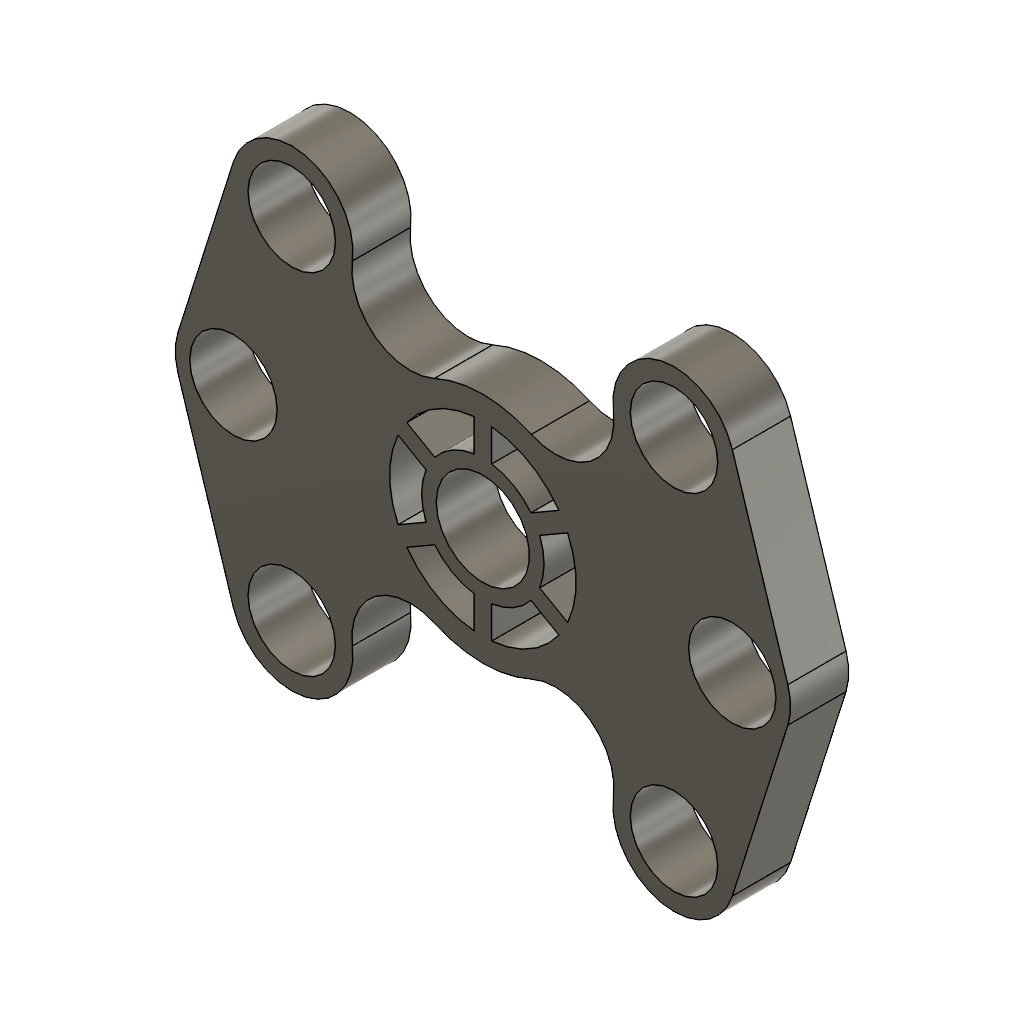
ex1.2 (Autodesk Fusion 360 design; units mm, degrees)
part number: 2026-10-12-15-41-16-369
Autodesk Fusion 360 part; units mm, degrees
sketch "Sketch1" plane through (0, 0, 0) normal (0, 0, 1) x (1, 0, 0)
  circle A0 centre (0, 0) radius 16
  circle A1 centre (0, 0) radius 40
  line L0 (-3, 20.7846) -> (-3, 31.8591)
  line L1 (-16.5, -12.9904) -> (-26.0908, -18.5276)
  line L2 (19.5, -7.7942) -> (29.0908, -13.3315)
  line L3 (3, 20.7846) -> (3, 31.8591)
  line L4 (-19.5, 7.7942) -> (-29.0908, 13.3315)
  line L5 (-16.5, 12.9904) -> (-26.0908, 18.5276)
  line L6 (-19.5, -7.7942) -> (-29.0908, -13.3315)
  line L7 (3, -20.7846) -> (3, -31.8591)
  line L8 (-3, -20.7846) -> (-3, -31.8591)
  line L9 (19.5, -7.7942) -> (29.0908, -13.3315)
  line L10 (16.5, -12.9904) -> (26.0908, -18.5276)
  line L11 (16.5, 12.9904) -> (26.0908, 18.5276)
  line L12 (19.5, 7.7942) -> (29.0908, 13.3315)
  line L13 (0, 60) -> (0, 40)
  line L14 (0, 60) -> (0, 40)
  arc A2 (16.5, 12.9904) -> (3, 20.7846) centre (0, 0) ccw
  arc A3 (26.0908, 18.5276) -> (3, 31.8591) centre (0, 0) ccw
  arc A4 (-3, 31.8591) -> (-26.0908, 18.5276) centre (0, 0) ccw
  arc A5 (-3, 20.7846) -> (-16.5, 12.9904) centre (0, 0) ccw
  arc A6 (-19.5, 7.7942) -> (-19.5, -7.7942) centre (0, 0) ccw
  arc A7 (-29.0908, 13.3315) -> (-29.0908, -13.3315) centre (0, 0) ccw
  arc A8 (19.5, -7.7942) -> (19.5, 7.7942) centre (0, 0) ccw
  arc A9 (29.0908, -13.3315) -> (29.0908, 13.3315) centre (0, 0) ccw
  arc A10 (-16.5, -12.9904) -> (-3, -20.7846) centre (0, 0) ccw
  arc A11 (3, -20.7846) -> (16.5, -12.9904) centre (0, 0) ccw
  arc A12 (-26.0908, -18.5276) -> (-3, -31.8591) centre (0, 0) ccw
  arc A13 (3, -31.8591) -> (26.0908, -18.5276) centre (0, 0) ccw
  line L15 (0, 16) -> (0, -16)
  line L16 (0, -40) -> (0, -55)
  line L17 (0, 16) -> (0, -16)
  line L18 (0, -40) -> (0, -55)
  line L19 (0, 0) -> (-65.5914, 0)
  line L20 (-65.5914, 0) -> (-85.5914, 0)
  circle A14 centre (-65.5914, 60) radius 15
  circle A15 centre (-65.5914, 60) radius 21
  circle A16 centre (-85.5914, 0) radius 15
  circle A17 centre (-85.5914, 0) radius 20
  line L21 (0, 0) -> (-65.5914, 0)
  circle A18 centre (-65.5914, -60) radius 21
  circle A19 centre (-65.5914, -60) radius 15
  line L22 (-85.6162, 66.325) -> (-104.6627, 6.0238)
  line L23 (-104.6627, -6.0238) -> (-85.6162, -66.325)
  line L24 (0, 100) -> (0, -100)
  arc A20 (-16.6355, -36.3767) -> (-44.7767, -57.2162) centre (-24.9532, -54.565) ccw
  arc A21 (-44.7767, 57.2162) -> (-16.6355, 36.3767) centre (-24.9532, 54.565) ccw
  circle A22 centre (85.5914, 0) radius 15
  line L25 (104.6627, -6.0238) -> (85.6162, -66.325)
  line L26 (85.6162, 66.325) -> (104.6627, 6.0238)
  circle A23 centre (85.5914, 0) radius 20
  circle A24 centre (65.5914, -60) radius 15
  circle A25 centre (65.5914, -60) radius 21
  arc A26 (44.7767, -57.2162) -> (16.6355, -36.3767) centre (24.9532, -54.565) ccw
  arc A27 (16.6355, 36.3767) -> (44.7767, 57.2162) centre (24.9532, 54.565) ccw
  circle A28 centre (65.5914, 60) radius 21
  circle A29 centre (65.5914, 60) radius 15
  dimension "d1" = 32
  dimension "d2" = 42
  dimension "d3" = 64
  dimension "d6" = 80
  dimension "d7" = 3
  dimension "d9" = 360
  dimension "d11" = 360
  dimension "d12" = 20
  dimension "d13" = 60
  dimension "d15" = 30
  dimension "d16" = 42
  dimension "d17" = 30
  dimension "d18" = 40
  dimension "d19" = 40
  dimension "d20" = 40
  constraint coincident A0.centre A1.centre
  constraint concentric A4 A5
  constraint vertical L14
  constraint concentric A1 A4
  constraint vertical L0
  constraint symmetric L0.start L3.start L17
  constraint symmetric L0.end L3.end L14
  constraint coincident A0 L15.start
  constraint collinear L13 L15
  constraint coincident A1 L13.end
  constraint collinear L14 L17
  constraint concentric A2 A5
  constraint concentric A3 A4
  constraint concentric A4 A7
  constraint concentric A5 A6
  constraint concentric A6 A10
  constraint concentric A7 A12
  constraint concentric A8 A11
  constraint concentric A9 A13
  constraint concentric A10 A11
  constraint concentric A12 A13
  constraint coincident A0 L15.end
  constraint coincident A1 L16.start
  constraint collinear L15 L16
  constraint collinear L17 L18
  constraint perpendicular L15 L19
  constraint parallel L19 L20
  constraint concentric A14 A15
  constraint coincident L20.end A16.centre
  constraint concentric A16 A17
  constraint symmetric A0.centre L19 A1.centre
  constraint symmetric L20.start L19 L21.end
  constraint symmetric L19 A14 A19
  constraint symmetric L19 A15 A18
  constraint tangent A15 L22
  constraint tangent A17 L22
  constraint coincident A17 L22.end
  constraint coincident A15 L22.start
  constraint tangent A17 L23
  constraint tangent A18 L23
  constraint coincident A18 L23.end
  constraint coincident A17 L23.start
  constraint parallel L16 L24
  constraint tangent A1 A20
  constraint tangent A18 A20
  constraint tangent A1 A21
  constraint tangent A15 A21
  constraint coincident A18 A20.end
  constraint coincident A1 A20.start
  constraint coincident A1 A21.end
  constraint coincident A15 A21.start
  constraint symmetric A14 L24 A29
  constraint symmetric A15 L24 A28
  constraint symmetric A16 L24 A22
  constraint symmetric A17 L24 A23
  constraint symmetric A18 L24 A25
  constraint symmetric A19 L24 A24
  constraint symmetric L22.end L24 L26.end
  constraint symmetric L22.start L24 L26.start
  constraint symmetric L23.end L24 L25.end
  constraint symmetric L23.start L24 L25.start
  constraint symmetric L24 A20.end A26.start
  constraint symmetric L24 A20.start A26.end
  constraint symmetric L24 A20 A26
  constraint symmetric L24 A21.end A27.start
  constraint symmetric L24 A21.start A27.end
  constraint symmetric L24 A21 A27
  measures "d1" diameter of A0
  measures "d2" diameter of A5
  measures "d3" diameter of A4
  measures "d6" diameter of A1
  measures "d7" distance of L0 L17
  measures "d12" distance of L19.end L20.end
  measures "d13" distance of L19.end A14.centre
  measures "d15" diameter of A14
  measures "d16" diameter of A15
  measures "d17" diameter of A16
  measures "d18" diameter of A17
  measures "d19" diameter of A20
  measures "d20" diameter of A21
extrude "Extrude1" add sketch "Sketch1" along normal blind 20 contours A0 A1 L24 | A0 A1 L4 A6 A7 L19 L21 L24 | A0 A1 L6 A6 A7 L19 L21 L24 | A1 L25 L26 A23 A25 A26 A27 A28 | A1 L19 A15 A17 L21 L22 A21 | A1 L19 A17 L21 A18 L23 A20 | A28 | A15 | A18 | A25 | A17 | A23
